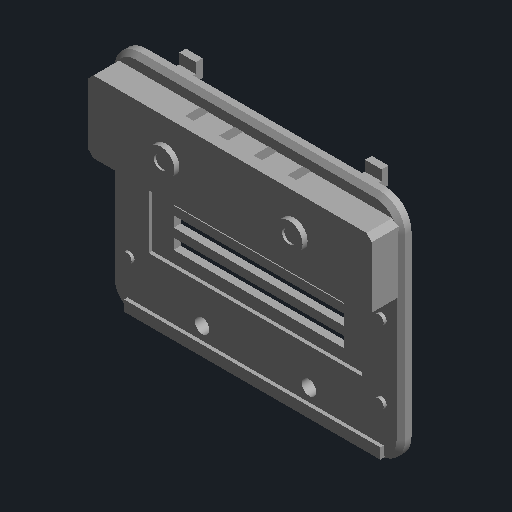
# Autodesk Inventor part: Torso_pecho
Saved by Autodesk Inventor 2027 (Build 310192060, 192F)
## iProperties
Part Number: Torso_pecho
Material: Genérico
Document SubType Name: Modelado
Designer: rodri
Appearance: Por defecto
Author: rodri
Autodesk Inventor part; units mm, degrees
ref_plane "Plano de trabajo1" through (0, 0, 49.2) normal (0, 0, 1) x (1, 0, 0)
sketch "Boceto1" plane through (0, 0, 49.2) normal (0, 0, 1) x (1, 0, 0)
  line L0 (-34, 4) -> (34, 4)
  line L1 (34, 4) -> (34, 57.7)
  line L2 (34, 57.7) -> (-34, 57.7)
  line L3 (-34, 57.7) -> (-34, 4)
  constraints: 8 end point, 2 parallel, 1 horizontal, 1 perpendicular
extrude "Extrusión1" add sketch "Boceto1" along normal blind 2.5
fillet "Empalme1" radius 6 4 edges at (-34, 4, 50.45) (-34, 57.7, 50.45) (34, 57.7, 50.45) (34, 4, 50.45)
ref_plane "Plano de trabajo2" through (0, 0, 49.1) normal (0, 0, 1) x (1, 0, 0)
sketch "Boceto2" plane through (0, 0, 49.1) normal (0, 0, 1) x (1, 0, 0)
  circle A0 centre (12.5, 10.5) radius 1.7
  circle A1 centre (-12.5, 10.5) radius 1.7
  constraints: 2 centre point
extrude "Extrusión2" cut sketch "Boceto2" along normal blind 2.7
ref_plane "Plano de trabajo3" through (0, 0, 44.3) normal (0, 0, 1) x (1, 0, 0)
sketch "Boceto3" plane through (0, 0, 44.3) normal (0, 0, 1) x (1, 0, 0)
  line L0 (19.8, 53.4) -> (23.7, 53.4)
  line L1 (23.7, 53.4) -> (23.7, 55)
  line L2 (23.7, 55) -> (19.8, 55)
  line L3 (19.8, 55) -> (19.8, 53.4)
  constraints: 8 end point, 2 parallel, 1 horizontal, 1 perpendicular
extrude "Extrusión3" add sketch "Boceto3" along normal blind 4.91
ref_plane "Plano de trabajo4" through (0, 0, 44.3) normal (0, 0, 1) x (1, 0, 0)
sketch "Boceto4" plane through (0, 0, 44.3) normal (0, 0, 1) x (1, 0, 0)
  line L0 (19.8, 53.4) -> (23.7, 53.4)
  line L1 (23.7, 53.4) -> (23.7, 57.4)
  line L2 (23.7, 57.4) -> (19.8, 57.4)
  line L3 (19.8, 57.4) -> (19.8, 53.4)
  constraints: 8 end point, 2 parallel, 1 horizontal, 1 perpendicular
extrude "Extrusión4" add sketch "Boceto4" along normal blind 1.6
ref_plane "Plano de trabajo5" through (0, 0, 44.3) normal (0, 0, 1) x (1, 0, 0)
sketch "Boceto5" plane through (0, 0, 44.3) normal (0, 0, 1) x (1, 0, 0)
  line L0 (-23.7, 53.4) -> (-19.8, 53.4)
  line L1 (-19.8, 53.4) -> (-19.8, 55)
  line L2 (-19.8, 55) -> (-23.7, 55)
  line L3 (-23.7, 55) -> (-23.7, 53.4)
  constraints: 8 end point, 2 parallel, 1 horizontal, 1 perpendicular
extrude "Extrusión5" add sketch "Boceto5" along normal blind 4.91
ref_plane "Plano de trabajo6" through (0, 0, 44.3) normal (0, 0, 1) x (1, 0, 0)
sketch "Boceto6" plane through (0, 0, 44.3) normal (0, 0, 1) x (1, 0, 0)
  line L0 (-23.7, 53.4) -> (-19.8, 53.4)
  line L1 (-19.8, 53.4) -> (-19.8, 57.4)
  line L2 (-19.8, 57.4) -> (-23.7, 57.4)
  line L3 (-23.7, 57.4) -> (-23.7, 53.4)
  constraints: 8 end point, 2 parallel, 1 horizontal, 1 perpendicular
extrude "Extrusión6" add sketch "Boceto6" along normal blind 1.6
ref_plane "Plano de trabajo7" through (0, 0, 50.9) normal (0, 0, 1) x (1, 0, 0)
sketch "Boceto7" plane through (0, 0, 50.9) normal (0, 0, 1) x (1, 0, 0)
  line L0 (-25, 19) -> (25, 19)
  line L1 (25, 19) -> (25, 45)
  line L2 (25, 45) -> (-25, 45)
  line L3 (-25, 45) -> (-25, 19)
  constraints: 8 end point, 2 parallel, 1 horizontal, 1 perpendicular
extrude "Extrusión7" cut sketch "Boceto7" along normal blind 0.9
ref_plane "Plano de trabajo8" through (0, 0, 49.1) normal (0, 0, 1) x (1, 0, 0)
sketch "Boceto8" plane through (0, 0, 49.1) normal (0, 0, 1) x (1, 0, 0)
  line L0 (-20, 21.75) -> (20, 21.75)
  line L1 (20, 21.75) -> (20, 24.25)
  line L2 (20, 24.25) -> (-20, 24.25)
  line L3 (-20, 24.25) -> (-20, 21.75)
  constraints: 8 end point, 2 parallel, 1 horizontal, 1 perpendicular
extrude "Extrusión8" cut sketch "Boceto8" along normal blind 2.7
ref_plane "Plano de trabajo9" through (0, 0, 49.1) normal (0, 0, 1) x (1, 0, 0)
sketch "Boceto9" plane through (0, 0, 49.1) normal (0, 0, 1) x (1, 0, 0)
  line L0 (-20, 26.25) -> (20, 26.25)
  line L1 (20, 26.25) -> (20, 28.75)
  line L2 (20, 28.75) -> (-20, 28.75)
  line L3 (-20, 28.75) -> (-20, 26.25)
  constraints: 8 end point, 2 parallel, 1 horizontal, 1 perpendicular
extrude "Extrusión9" cut sketch "Boceto9" along normal blind 2.7
ref_plane "Plano de trabajo10" through (0, 0, 49.1) normal (0, 0, 1) x (1, 0, 0)
sketch "Boceto10" plane through (0, 0, 49.1) normal (0, 0, 1) x (1, 0, 0)
  line L0 (-20, 30.75) -> (20, 30.75)
  line L1 (20, 30.75) -> (20, 33.25)
  line L2 (20, 33.25) -> (-20, 33.25)
  line L3 (-20, 33.25) -> (-20, 30.75)
  constraints: 8 end point, 2 parallel, 1 horizontal, 1 perpendicular
extrude "Extrusión10" cut sketch "Boceto10" along normal blind 2.7
ref_plane "Plano de trabajo11" through (0, 0, 49.2) normal (0, 0, 1) x (1, 0, 0)
sketch "Boceto11" plane through (0, 0, 49.2) normal (0, 0, 1) x (1, 0, 0)
  line L0 (-33.2, 37.75) -> (33.2, 37.75)
  line L1 (33.2, 37.75) -> (33.2, 54.55)
  line L2 (33.2, 54.55) -> (-33.2, 54.55)
  line L3 (-33.2, 54.55) -> (-33.2, 37.75)
  constraints: 8 end point, 2 parallel, 1 horizontal, 1 perpendicular
extrude "Extrusión11" add sketch "Boceto11" along normal blind 8.5
ref_plane "Plano de trabajo12" through (0, 0, 49.1) normal (0, 0, 1) x (1, 0, 0)
sketch "Boceto12" plane through (0, 0, 49.1) normal (0, 0, 1) x (1, 0, 0)
  line L0 (-32, 39.75) -> (22.75, 39.75)
  line L1 (22.75, 39.75) -> (22.75, 52.55)
  line L2 (22.75, 52.55) -> (-32, 52.55)
  line L3 (-32, 52.55) -> (-32, 39.75)
  constraints: 8 end point, 2 parallel, 1 horizontal, 1 perpendicular
extrude "Extrusión12" cut sketch "Boceto12" along normal blind 6.6
ref_plane "Plano de trabajo13" through (0, 0, 49.1) normal (0, 0, 1) x (1, 0, 0)
sketch "Boceto13" plane through (0, 0, 49.1) normal (0, 0, 1) x (1, 0, 0)
  line L0 (24.75, 39.75) -> (31.2, 39.75)
  line L1 (31.2, 39.75) -> (31.2, 52.55)
  line L2 (31.2, 52.55) -> (24.75, 52.55)
  line L3 (24.75, 52.55) -> (24.75, 39.75)
  constraints: 8 end point, 2 parallel, 1 horizontal, 1 perpendicular
extrude "Extrusión13" cut sketch "Boceto13" along normal blind 6.6
ref_plane "Plano de trabajo14" through (0, 0, 49.7) normal (0, 0, 1) x (1, 0, 0)
sketch "Boceto14" plane through (0, 0, 49.7) normal (0, 0, 1) x (1, 0, 0)
  line L0 (-13, 52.45) -> (-11, 52.45)
  line L1 (-11, 52.45) -> (-11, 54.65)
  line L2 (-11, 54.65) -> (-13, 54.65)
  line L3 (-13, 54.65) -> (-13, 52.45)
  constraints: 8 end point, 2 parallel, 1 horizontal, 1 perpendicular
extrude "Extrusión14" cut sketch "Boceto14" along normal blind 5.5
ref_plane "Plano de trabajo15" through (0, 0, 49.7) normal (0, 0, 1) x (1, 0, 0)
sketch "Boceto15" plane through (0, 0, 49.7) normal (0, 0, 1) x (1, 0, 0)
  line L0 (-5, 52.45) -> (-3, 52.45)
  line L1 (-3, 52.45) -> (-3, 54.65)
  line L2 (-3, 54.65) -> (-5, 54.65)
  line L3 (-5, 54.65) -> (-5, 52.45)
  constraints: 8 end point, 2 parallel, 1 horizontal, 1 perpendicular
extrude "Extrusión15" cut sketch "Boceto15" along normal blind 5.5
ref_plane "Plano de trabajo16" through (0, 0, 49.7) normal (0, 0, 1) x (1, 0, 0)
sketch "Boceto16" plane through (0, 0, 49.7) normal (0, 0, 1) x (1, 0, 0)
  line L0 (3, 52.45) -> (5, 52.45)
  line L1 (5, 52.45) -> (5, 54.65)
  line L2 (5, 54.65) -> (3, 54.65)
  line L3 (3, 54.65) -> (3, 52.45)
  constraints: 8 end point, 2 parallel, 1 horizontal, 1 perpendicular
extrude "Extrusión16" cut sketch "Boceto16" along normal blind 5.5
ref_plane "Plano de trabajo17" through (0, 0, 49.7) normal (0, 0, 1) x (1, 0, 0)
sketch "Boceto17" plane through (0, 0, 49.7) normal (0, 0, 1) x (1, 0, 0)
  line L0 (11, 52.45) -> (13, 52.45)
  line L1 (13, 52.45) -> (13, 54.65)
  line L2 (13, 54.65) -> (11, 54.65)
  line L3 (11, 54.65) -> (11, 52.45)
  constraints: 8 end point, 2 parallel, 1 horizontal, 1 perpendicular
extrude "Extrusión17" cut sketch "Boceto17" along normal blind 5.5
ref_plane "Plano de trabajo18" through (0, 0, 57.69) normal (0, 0, 1) x (1, 0, 0)
sketch "Boceto18" plane through (0, 0, 57.69) normal (0, 0, 1) x (1, 0, 0)
  circle A0 centre (15, 46) radius 3.2
  circle A1 centre (-15, 46) radius 3.2
  constraints: 2 centre point
extrude "Extrusión18" add sketch "Boceto18" along normal blind 1.21
ref_plane "Plano de trabajo19" through (0, 0, 58.4) normal (0, 0, 1) x (1, 0, 0)
sketch "Boceto19" plane through (0, 0, 58.4) normal (0, 0, 1) x (1, 0, 0)
  circle A0 centre (15, 46) radius 1.6
  circle A1 centre (-15, 46) radius 1.6
  constraints: 2 centre point
extrude "Extrusión19" cut sketch "Boceto19" along normal blind 0.6
ref_plane "Plano de trabajo20" through (0, 0, 51.69) normal (0, 0, 1) x (1, 0, 0)
sketch "Boceto20" plane through (0, 0, 51.69) normal (0, 0, 1) x (1, 0, 0)
  line L0 (-30, 5) -> (30, 5)
  line L1 (30, 5) -> (30, 7.5)
  line L2 (30, 7.5) -> (-30, 7.5)
  line L3 (-30, 7.5) -> (-30, 5)
  constraints: 8 end point, 2 parallel, 1 horizontal, 1 perpendicular
extrude "Extrusión20" add sketch "Boceto20" along normal blind 0.81
ref_plane "Plano de trabajo21" through (0, 0, 51.69) normal (0, 0, 1) x (1, 0, 0)
sketch "Boceto21" plane through (0, 0, 51.69) normal (0, 0, 1) x (1, 0, 0)
  circle A0 centre (29.5, 16) radius 1.2
  circle A1 centre (29.5, 33) radius 1.2
  circle A2 centre (-29.5, 16) radius 1.2
  circle A3 centre (-29.5, 33) radius 1.2
  constraints: 4 centre point
extrude "Extrusión21" add sketch "Boceto21" along normal blind 0.71
chamfer "Chaflán1" distance 1 angle 45 8 edges at (32.2426, 5.7574, 51.7) (34, 30.85, 51.7) (32.2426, 55.9426, 51.7) (0, 57.7, 51.7) (-32.2426, 55.9426, 51.7) (-34, 30.85, 51.7) (-32.2426, 5.7574, 51.7) (0, 4, 51.7)
ref_plane "Plano de trabajo22" through (0, 0, 0) normal (0, 1, 0) x (0, 0, 1)
ref_plane "Plano de trabajo23" through (0, 0, 0) normal (1, 0, 0) x (0, 0, -1)
chamfer "Chaflán2" distance 1.25 angle 45 4 edges at (-33.2, 54.55, 54.2351) (-33.2, 37.75, 54.6) (33.2, 54.55, 54.2351) (33.2, 37.75, 54.6)
ref_plane "Plano de trabajo24" through (0, 0, 0) normal (0, 1, 0) x (0, 0, 1)
ref_plane "Plano de trabajo25" through (0, 0, 0) normal (1, 0, 0) x (0, 0, -1)
